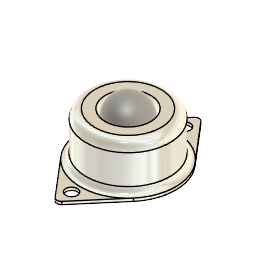
AGV_2026 (Autodesk Fusion 360 archive; units mm, degrees)
design "caster wheel v2"
Autodesk Fusion 360 part; units mm, degrees
sketch "Sketch1" plane through (0, 0, 0) normal (0, 0, 1) x (1, 0, 0)
  circle A0 centre (0, 0) radius 16.25
  line L0 (0, 21.25) -> (0, -21.25) construction
  circle A1 centre (0, 19.25) radius 2
  line L1 (0, 0) -> (16.25, 0) construction
  circle A2 centre (0, -19.25) radius 2
  line L2 (0, 21.25) -> (0, 24.25) construction
  circle A3 centre (0, 22.75) radius 1.5
  line L3 (-1.142, 23.7225) -> (-12.3718, 10.5357)
  line L4 (1.142, 23.7225) -> (12.3718, 10.5357)
  circle A4 centre (0, 0) radius 14.25
  circle A5 centre (0, -22.75) radius 1.5
  line L5 (1.142, -23.7225) -> (12.3718, -10.5357)
  line L6 (-1.142, -23.7225) -> (-12.3718, -10.5357)
  dimension "d1" = 32.5
  dimension "d2" = 42.5
  dimension "d3" = 4
  dimension "d4" = 3
  dimension "d5" = -2
  constraint coincident A0.centre L1.start
  constraint vertical L0
  constraint midpoint A0.centre L0
  constraint coincident L0.start A1
  constraint coincident L0 A1.centre
  constraint coincident A0 L1.end
  constraint perpendicular L0 L1
  constraint symmetric A1 L1 A2
  constraint parallel L0 L2
  constraint coincident L0.start A3
  constraint tangent A1 A3
  constraint coincident L2.end A3
  constraint coincident A3 L3.start
  constraint coincident A0 L3.end
  constraint tangent A3 L3
  constraint tangent A0 L3
  constraint coincident A3 L4.start
  constraint coincident A0 L4.end
  constraint tangent A3 L4
  constraint tangent A0 L4
  constraint symmetric L1 A3 A5
  constraint symmetric L1 L3.start L6.start
  constraint symmetric L1 L3.end L6.end
  constraint symmetric L1 L4.start L5.start
  constraint symmetric L1 L4.end L5.end
  measures "d1" diameter of A0
  measures "d2" distance of L0.start L0.end
  measures "d3" diameter of A1
  measures "d4" distance of L0.start L2.end
extrude "Extrude1" add sketch "Sketch1" along normal blind 1 contours A0 | A0 A3 L3 L4 | A0 A5 L5 L6 | A3 | A5 | A4 makes body 1
extrude "Extrude2" add sketch "Sketch1" along normal blind 15 from surface at 1 contours A4 bodies 1
fillet "Fillet1" radius 2 1 edges at (-13.2857, 5.153, 1) on bodies 1
fillet "Fillet1" radius 3 1 edges at (-13.2857, -5.153, 16) on bodies 1
sketch "Sketch2" plane through (0, 0, 16) normal (0, 0, 1) x (-1, 0, 0)
  circle A0 centre (0, 0) radius 11.25
  circle A1 centre (0, 0) radius 7.75
  dimension "d15" = 15.5
  constraint concentric A0 A1
  measures "d15" diameter of A1
extrude "Extrude3" cut sketch "Sketch2" against normal blind 10 contours A1 bodies 1
ref_plane "WorkPlane1" through (0, 0, 13.5) normal (0, 0, 1) x (1, 0, 0)
sketch "Sketch3" plane through (0, 0, 13.5) normal (0, 0, 1) x (1, 0, 0)
sphere "SpherePrimitive1" add diameter 14 placed x (1, 0, 0) y (0, 1, 0) z (0, 0, 1) at (0, 0, 13.5) separate body makes body 2 in component "Sphere"
copy_body "Body->Comp1" bodies 1 removing the originals makes body 3 in component "Case"
component "Sphere" placed x (1, 0, 0) y (0, 1, 0) z (0, 0, 1) at (0, 0, 0)
component "Case" placed x (1, 0, 0) y (0, 1, 0) z (0, 0, 1) at (0, 0, 0)
